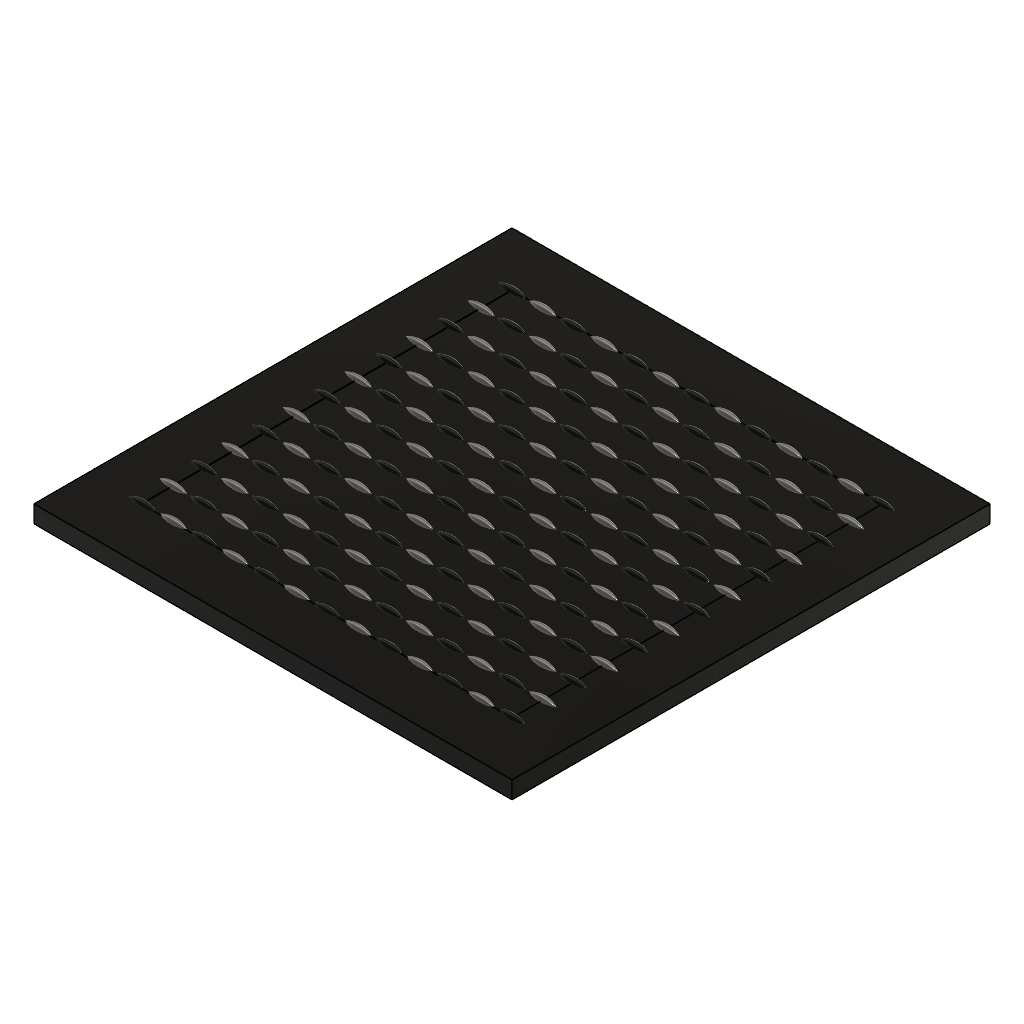
SCENE-draft (Autodesk Fusion 360 design; units mm, degrees)
Autodesk Fusion 360 part; units mm, degrees
(part 1 of 2)
ref_plane "工作平面1" through (0, 0, -12) normal (0, 0, 1) x (1, 0, 0) in component "scene_board"
sketch "草图1" plane through (0, 0, -12) normal (0, 0, 1) x (1, 0, 0) in component "scene_board"
  line L0 (-165, -165) -> (165, -165)
  line L1 (165, -165) -> (165, 165)
  line L2 (165, 165) -> (-165, 165)
  line L3 (-165, 165) -> (-165, -165)
extrude "拉伸1" add sketch "草图1" along normal blind 12 makes body 1 in component "scene_board"
ref_plane "工作平面2" through (0, 0, 0) normal (0, 0, 1) x (1, 0, 0) in component "scene_board"
sketch "草图2" plane through (0, 0, 0) normal (0, 0, 1) x (1, 0, 0) in component "scene_board"
  line L0 (-127.5, -127.9) -> (127.5, -127.9)
  line L1 (127.5, -127.9) -> (127.5, -127.1)
  line L2 (127.5, -127.1) -> (-127.5, -127.1)
  line L3 (-127.5, -127.1) -> (-127.5, -127.9)
  line L4 (-127.9, -127.5) -> (-127.1, -127.5)
  line L5 (-127.1, -127.5) -> (-127.1, 127.5)
  line L6 (-127.1, 127.5) -> (-127.9, 127.5)
  line L7 (-127.9, 127.5) -> (-127.9, -127.5)
  line L8 (-127.5, -106.65) -> (127.5, -106.65)
  line L9 (127.5, -106.65) -> (127.5, -105.85)
  line L10 (127.5, -105.85) -> (-127.5, -105.85)
  line L11 (-127.5, -105.85) -> (-127.5, -106.65)
  line L12 (-106.65, -127.5) -> (-105.85, -127.5)
  line L13 (-105.85, -127.5) -> (-105.85, 127.5)
  line L14 (-105.85, 127.5) -> (-106.65, 127.5)
  line L15 (-106.65, 127.5) -> (-106.65, -127.5)
  line L16 (-127.5, -85.4) -> (127.5, -85.4)
  line L17 (127.5, -85.4) -> (127.5, -84.6)
  line L18 (127.5, -84.6) -> (-127.5, -84.6)
  line L19 (-127.5, -84.6) -> (-127.5, -85.4)
  line L20 (-85.4, -127.5) -> (-84.6, -127.5)
  line L21 (-84.6, -127.5) -> (-84.6, 127.5)
  line L22 (-84.6, 127.5) -> (-85.4, 127.5)
  line L23 (-85.4, 127.5) -> (-85.4, -127.5)
  line L24 (-127.5, -64.15) -> (127.5, -64.15)
  line L25 (127.5, -64.15) -> (127.5, -63.35)
  line L26 (127.5, -63.35) -> (-127.5, -63.35)
  line L27 (-127.5, -63.35) -> (-127.5, -64.15)
  line L28 (-64.15, -127.5) -> (-63.35, -127.5)
  line L29 (-63.35, -127.5) -> (-63.35, 127.5)
  line L30 (-63.35, 127.5) -> (-64.15, 127.5)
  line L31 (-64.15, 127.5) -> (-64.15, -127.5)
  line L32 (-127.5, -42.9) -> (127.5, -42.9)
  line L33 (127.5, -42.9) -> (127.5, -42.1)
  line L34 (127.5, -42.1) -> (-127.5, -42.1)
  line L35 (-127.5, -42.1) -> (-127.5, -42.9)
  line L36 (-42.9, -127.5) -> (-42.1, -127.5)
  line L37 (-42.1, -127.5) -> (-42.1, 127.5)
  line L38 (-42.1, 127.5) -> (-42.9, 127.5)
  line L39 (-42.9, 127.5) -> (-42.9, -127.5)
  line L40 (-127.5, -21.65) -> (127.5, -21.65)
  line L41 (127.5, -21.65) -> (127.5, -20.85)
  line L42 (127.5, -20.85) -> (-127.5, -20.85)
  line L43 (-127.5, -20.85) -> (-127.5, -21.65)
  line L44 (-21.65, -127.5) -> (-20.85, -127.5)
  line L45 (-20.85, -127.5) -> (-20.85, 127.5)
  line L46 (-20.85, 127.5) -> (-21.65, 127.5)
  line L47 (-21.65, 127.5) -> (-21.65, -127.5)
  line L48 (-127.5, -0.4) -> (127.5, -0.4)
  line L49 (127.5, -0.4) -> (127.5, 0.4)
  line L50 (127.5, 0.4) -> (-127.5, 0.4)
  line L51 (-127.5, 0.4) -> (-127.5, -0.4)
  line L52 (-0.4, -127.5) -> (0.4, -127.5)
  line L53 (0.4, -127.5) -> (0.4, 127.5)
  line L54 (0.4, 127.5) -> (-0.4, 127.5)
  line L55 (-0.4, 127.5) -> (-0.4, -127.5)
  line L56 (-127.5, 20.85) -> (127.5, 20.85)
  line L57 (127.5, 20.85) -> (127.5, 21.65)
  line L58 (127.5, 21.65) -> (-127.5, 21.65)
  line L59 (-127.5, 21.65) -> (-127.5, 20.85)
  line L60 (20.85, -127.5) -> (21.65, -127.5)
  line L61 (21.65, -127.5) -> (21.65, 127.5)
  line L62 (21.65, 127.5) -> (20.85, 127.5)
  line L63 (20.85, 127.5) -> (20.85, -127.5)
  line L64 (-127.5, 42.1) -> (127.5, 42.1)
  line L65 (127.5, 42.1) -> (127.5, 42.9)
  line L66 (127.5, 42.9) -> (-127.5, 42.9)
  line L67 (-127.5, 42.9) -> (-127.5, 42.1)
  line L68 (42.1, -127.5) -> (42.9, -127.5)
  line L69 (42.9, -127.5) -> (42.9, 127.5)
  line L70 (42.9, 127.5) -> (42.1, 127.5)
  line L71 (42.1, 127.5) -> (42.1, -127.5)
  line L72 (-127.5, 63.35) -> (127.5, 63.35)
  line L73 (127.5, 63.35) -> (127.5, 64.15)
  line L74 (127.5, 64.15) -> (-127.5, 64.15)
  line L75 (-127.5, 64.15) -> (-127.5, 63.35)
  line L76 (63.35, -127.5) -> (64.15, -127.5)
  line L77 (64.15, -127.5) -> (64.15, 127.5)
  line L78 (64.15, 127.5) -> (63.35, 127.5)
  line L79 (63.35, 127.5) -> (63.35, -127.5)
  line L80 (-127.5, 84.6) -> (127.5, 84.6)
  line L81 (127.5, 84.6) -> (127.5, 85.4)
  line L82 (127.5, 85.4) -> (-127.5, 85.4)
  line L83 (-127.5, 85.4) -> (-127.5, 84.6)
  line L84 (84.6, -127.5) -> (85.4, -127.5)
  line L85 (85.4, -127.5) -> (85.4, 127.5)
  line L86 (85.4, 127.5) -> (84.6, 127.5)
  line L87 (84.6, 127.5) -> (84.6, -127.5)
  line L88 (-127.5, 105.85) -> (127.5, 105.85)
  line L89 (127.5, 105.85) -> (127.5, 106.65)
  line L90 (127.5, 106.65) -> (-127.5, 106.65)
  line L91 (-127.5, 106.65) -> (-127.5, 105.85)
  line L92 (105.85, -127.5) -> (106.65, -127.5)
  line L93 (106.65, -127.5) -> (106.65, 127.5)
  line L94 (106.65, 127.5) -> (105.85, 127.5)
  line L95 (105.85, 127.5) -> (105.85, -127.5)
  line L96 (-127.5, 127.1) -> (127.5, 127.1)
  line L97 (127.5, 127.1) -> (127.5, 127.9)
  line L98 (127.5, 127.9) -> (-127.5, 127.9)
  line L99 (-127.5, 127.9) -> (-127.5, 127.1)
  line L100 (127.1, -127.5) -> (127.9, -127.5)
  line L101 (127.9, -127.5) -> (127.9, 127.5)
  line L102 (127.9, 127.5) -> (127.1, 127.5)
  line L103 (127.1, 127.5) -> (127.1, -127.5)
extrude "拉伸2" cut sketch "草图2" against normal blind 0.3 bodies 1 in component "scene_board"
sketch "草图1 (2)" plane through (0, 0, 0) normal (0, 0, 1) x (1, 0, 0) in component "scene_go"
  line L0 (-139, -127.5) -> (-116, -127.5) construction
  arc A0 (-118, -127.5) -> (-137, -127.5) centre (-127.5, -146.4306) ccw
  arc A1 (-137, -127.5) -> (-118, -127.5) centre (-127.5, -108.5694) ccw
revolve "旋转1" add sketch "草图1 (2)" angle 360 about axis through (-139, -127.5, 0) along (1, 0, 0) separate body makes body 2 in component "scene_go"
sketch "草图2 (2)" plane through (0, 0, 0) normal (0, 0, 1) x (1, 0, 0) in component "scene_go"
  line L0 (-139, -106.25) -> (-116, -106.25) construction
  arc A0 (-118, -106.25) -> (-137, -106.25) centre (-127.5, -125.1806) ccw
  arc A1 (-137, -106.25) -> (-118, -106.25) centre (-127.5, -87.3194) ccw
revolve "旋转2" add sketch "草图2 (2)" angle 360 about axis through (-139, -106.25, 0) along (1, 0, 0) separate body makes body 3 in component "scene_go"
sketch "草图3" plane through (0, 0, 0) normal (0, 0, 1) x (1, 0, 0) in component "scene_go"
  line L0 (-139, -85) -> (-116, -85) construction
  arc A0 (-118, -85) -> (-137, -85) centre (-127.5, -103.9306) ccw
  arc A1 (-137, -85) -> (-118, -85) centre (-127.5, -66.0694) ccw
revolve "旋转3" add sketch "草图3" angle 360 about axis through (-139, -85, 0) along (1, 0, 0) separate body makes body 4 in component "scene_go"
sketch "草图4" plane through (0, 0, 0) normal (0, 0, 1) x (1, 0, 0) in component "scene_go"
  line L0 (-139, -63.75) -> (-116, -63.75) construction
  arc A0 (-118, -63.75) -> (-137, -63.75) centre (-127.5, -82.6806) ccw
  arc A1 (-137, -63.75) -> (-118, -63.75) centre (-127.5, -44.8194) ccw
revolve "旋转4" add sketch "草图4" angle 360 about axis through (-139, -63.75, 0) along (1, 0, 0) separate body makes body 5 in component "scene_go"
sketch "草图5" plane through (0, 0, 0) normal (0, 0, 1) x (1, 0, 0) in component "scene_go"
  line L0 (-139, -42.5) -> (-116, -42.5) construction
  arc A0 (-118, -42.5) -> (-137, -42.5) centre (-127.5, -61.4306) ccw
  arc A1 (-137, -42.5) -> (-118, -42.5) centre (-127.5, -23.5694) ccw
revolve "旋转5" add sketch "草图5" angle 360 about axis through (-139, -42.5, 0) along (1, 0, 0) separate body makes body 6 in component "scene_go"
sketch "草图6" plane through (0, 0, 0) normal (0, 0, 1) x (1, 0, 0) in component "scene_go"
  line L0 (-139, -21.25) -> (-116, -21.25) construction
  arc A0 (-118, -21.25) -> (-137, -21.25) centre (-127.5, -40.1806) ccw
  arc A1 (-137, -21.25) -> (-118, -21.25) centre (-127.5, -2.3194) ccw
revolve "旋转6" add sketch "草图6" angle 360 about axis through (-139, -21.25, 0) along (1, 0, 0) separate body makes body 7 in component "scene_go"
sketch "草图7" plane through (0, 0, 0) normal (0, 0, 1) x (1, 0, 0) in component "scene_go"
  line L0 (-139, 0) -> (-116, 0) construction
  arc A0 (-118, 0) -> (-137, 0) centre (-127.5, -18.9306) ccw
  arc A1 (-137, 0) -> (-118, 0) centre (-127.5, 18.9306) ccw
revolve "旋转7" add sketch "草图7" angle 360 about axis through (-139, 0, 0) along (1, 0, 0) separate body makes body 8 in component "scene_go"
sketch "草图8" plane through (0, 0, 0) normal (0, 0, 1) x (1, 0, 0) in component "scene_go"
  line L0 (-139, 21.25) -> (-116, 21.25) construction
  arc A0 (-118, 21.25) -> (-137, 21.25) centre (-127.5, 2.3194) ccw
  arc A1 (-137, 21.25) -> (-118, 21.25) centre (-127.5, 40.1806) ccw
revolve "旋转8" add sketch "草图8" angle 360 about axis through (-139, 21.25, 0) along (1, 0, 0) separate body makes body 9 in component "scene_go"
sketch "草图9" plane through (0, 0, 0) normal (0, 0, 1) x (1, 0, 0) in component "scene_go"
  line L0 (-139, 42.5) -> (-116, 42.5) construction
  arc A0 (-118, 42.5) -> (-137, 42.5) centre (-127.5, 23.5694) ccw
  arc A1 (-137, 42.5) -> (-118, 42.5) centre (-127.5, 61.4306) ccw
revolve "旋转9" add sketch "草图9" angle 360 about axis through (-139, 42.5, 0) along (1, 0, 0) separate body makes body 10 in component "scene_go"
sketch "草图10" plane through (0, 0, 0) normal (0, 0, 1) x (1, 0, 0) in component "scene_go"
  line L0 (-139, 63.75) -> (-116, 63.75) construction
  arc A0 (-118, 63.75) -> (-137, 63.75) centre (-127.5, 44.8194) ccw
  arc A1 (-137, 63.75) -> (-118, 63.75) centre (-127.5, 82.6806) ccw
revolve "旋转10" add sketch "草图10" angle 360 about axis through (-139, 63.75, 0) along (1, 0, 0) separate body makes body 11 in component "scene_go"
sketch "草图11" plane through (0, 0, 0) normal (0, 0, 1) x (1, 0, 0) in component "scene_go"
  line L0 (-139, 85) -> (-116, 85) construction
  arc A0 (-118, 85) -> (-137, 85) centre (-127.5, 66.0694) ccw
  arc A1 (-137, 85) -> (-118, 85) centre (-127.5, 103.9306) ccw
revolve "旋转11" add sketch "草图11" angle 360 about axis through (-139, 85, 0) along (1, 0, 0) separate body makes body 12 in component "scene_go"
sketch "草图12" plane through (0, 0, 0) normal (0, 0, 1) x (1, 0, 0) in component "scene_go"
  line L0 (-139, 106.25) -> (-116, 106.25) construction
  arc A0 (-118, 106.25) -> (-137, 106.25) centre (-127.5, 87.3194) ccw
  arc A1 (-137, 106.25) -> (-118, 106.25) centre (-127.5, 125.1806) ccw
revolve "旋转12" add sketch "草图12" angle 360 about axis through (-139, 106.25, 0) along (1, 0, 0) separate body makes body 13 in component "scene_go"
sketch "草图13" plane through (0, 0, 0) normal (0, 0, 1) x (1, 0, 0) in component "scene_go"
  line L0 (-139, 127.5) -> (-116, 127.5) construction
  arc A0 (-118, 127.5) -> (-137, 127.5) centre (-127.5, 108.5694) ccw
  arc A1 (-137, 127.5) -> (-118, 127.5) centre (-127.5, 146.4306) ccw
revolve "旋转13" add sketch "草图13" angle 360 about axis through (-139, 127.5, 0) along (1, 0, 0) separate body makes body 14 in component "scene_go"
sketch "草图14" plane through (0, 0, 0) normal (0, 0, 1) x (1, 0, 0) in component "scene_go"
  line L0 (-117.75, -127.5) -> (-94.75, -127.5) construction
  arc A0 (-96.75, -127.5) -> (-115.75, -127.5) centre (-106.25, -146.4306) ccw
  arc A1 (-115.75, -127.5) -> (-96.75, -127.5) centre (-106.25, -108.5694) ccw
revolve "旋转14" add sketch "草图14" angle 360 about axis through (-117.75, -127.5, 0) along (1, 0, 0) separate body makes body 15 in component "scene_go"
sketch "草图15" plane through (0, 0, 0) normal (0, 0, 1) x (1, 0, 0) in component "scene_go"
  line L0 (-117.75, -106.25) -> (-94.75, -106.25) construction
  arc A0 (-96.75, -106.25) -> (-115.75, -106.25) centre (-106.25, -125.1806) ccw
  arc A1 (-115.75, -106.25) -> (-96.75, -106.25) centre (-106.25, -87.3194) ccw
revolve "旋转15" add sketch "草图15" angle 360 about axis through (-117.75, -106.25, 0) along (1, 0, 0) separate body makes body 16 in component "scene_go"
sketch "草图16" plane through (0, 0, 0) normal (0, 0, 1) x (1, 0, 0) in component "scene_go"
  line L0 (-117.75, -85) -> (-94.75, -85) construction
  arc A0 (-96.75, -85) -> (-115.75, -85) centre (-106.25, -103.9306) ccw
  arc A1 (-115.75, -85) -> (-96.75, -85) centre (-106.25, -66.0694) ccw
revolve "旋转16" add sketch "草图16" angle 360 about axis through (-117.75, -85, 0) along (1, 0, 0) separate body makes body 17 in component "scene_go"
sketch "草图17" plane through (0, 0, 0) normal (0, 0, 1) x (1, 0, 0) in component "scene_go"
  line L0 (-117.75, -63.75) -> (-94.75, -63.75) construction
  arc A0 (-96.75, -63.75) -> (-115.75, -63.75) centre (-106.25, -82.6806) ccw
  arc A1 (-115.75, -63.75) -> (-96.75, -63.75) centre (-106.25, -44.8194) ccw
revolve "旋转17" add sketch "草图17" angle 360 about axis through (-117.75, -63.75, 0) along (1, 0, 0) separate body makes body 18 in component "scene_go"
sketch "草图18" plane through (0, 0, 0) normal (0, 0, 1) x (1, 0, 0) in component "scene_go"
  line L0 (-117.75, -42.5) -> (-94.75, -42.5) construction
  arc A0 (-96.75, -42.5) -> (-115.75, -42.5) centre (-106.25, -61.4306) ccw
  arc A1 (-115.75, -42.5) -> (-96.75, -42.5) centre (-106.25, -23.5694) ccw
revolve "旋转18" add sketch "草图18" angle 360 about axis through (-117.75, -42.5, 0) along (1, 0, 0) separate body makes body 19 in component "scene_go"
sketch "草图19" plane through (0, 0, 0) normal (0, 0, 1) x (1, 0, 0) in component "scene_go"
  line L0 (-117.75, -21.25) -> (-94.75, -21.25) construction
  arc A0 (-96.75, -21.25) -> (-115.75, -21.25) centre (-106.25, -40.1806) ccw
  arc A1 (-115.75, -21.25) -> (-96.75, -21.25) centre (-106.25, -2.3194) ccw
revolve "旋转19" add sketch "草图19" angle 360 about axis through (-117.75, -21.25, 0) along (1, 0, 0) separate body makes body 20 in component "scene_go"
sketch "草图20" plane through (0, 0, 0) normal (0, 0, 1) x (1, 0, 0) in component "scene_go"
  line L0 (-117.75, 0) -> (-94.75, 0) construction
  arc A0 (-96.75, 0) -> (-115.75, 0) centre (-106.25, -18.9306) ccw
  arc A1 (-115.75, 0) -> (-96.75, 0) centre (-106.25, 18.9306) ccw
revolve "旋转20" add sketch "草图20" angle 360 about axis through (-117.75, 0, 0) along (1, 0, 0) separate body makes body 21 in component "scene_go"
sketch "草图21" plane through (0, 0, 0) normal (0, 0, 1) x (1, 0, 0) in component "scene_go"
  line L0 (-117.75, 21.25) -> (-94.75, 21.25) construction
  arc A0 (-96.75, 21.25) -> (-115.75, 21.25) centre (-106.25, 2.3194) ccw
  arc A1 (-115.75, 21.25) -> (-96.75, 21.25) centre (-106.25, 40.1806) ccw
revolve "旋转21" add sketch "草图21" angle 360 about axis through (-117.75, 21.25, 0) along (1, 0, 0) separate body makes body 22 in component "scene_go"
sketch "草图22" plane through (0, 0, 0) normal (0, 0, 1) x (1, 0, 0) in component "scene_go"
  line L0 (-117.75, 42.5) -> (-94.75, 42.5) construction
  arc A0 (-96.75, 42.5) -> (-115.75, 42.5) centre (-106.25, 23.5694) ccw
  arc A1 (-115.75, 42.5) -> (-96.75, 42.5) centre (-106.25, 61.4306) ccw
revolve "旋转22" add sketch "草图22" angle 360 about axis through (-117.75, 42.5, 0) along (1, 0, 0) separate body makes body 23 in component "scene_go"
sketch "草图23" plane through (0, 0, 0) normal (0, 0, 1) x (1, 0, 0) in component "scene_go"
  line L0 (-117.75, 63.75) -> (-94.75, 63.75) construction
  arc A0 (-96.75, 63.75) -> (-115.75, 63.75) centre (-106.25, 44.8194) ccw
  arc A1 (-115.75, 63.75) -> (-96.75, 63.75) centre (-106.25, 82.6806) ccw
revolve "旋转23" add sketch "草图23" angle 360 about axis through (-117.75, 63.75, 0) along (1, 0, 0) separate body makes body 24 in component "scene_go"
sketch "草图24" plane through (0, 0, 0) normal (0, 0, 1) x (1, 0, 0) in component "scene_go"
  line L0 (-117.75, 85) -> (-94.75, 85) construction
  arc A0 (-96.75, 85) -> (-115.75, 85) centre (-106.25, 66.0694) ccw
  arc A1 (-115.75, 85) -> (-96.75, 85) centre (-106.25, 103.9306) ccw
revolve "旋转24" add sketch "草图24" angle 360 about axis through (-117.75, 85, 0) along (1, 0, 0) separate body makes body 25 in component "scene_go"
sketch "草图25" plane through (0, 0, 0) normal (0, 0, 1) x (1, 0, 0) in component "scene_go"
  line L0 (-117.75, 106.25) -> (-94.75, 106.25) construction
  arc A0 (-96.75, 106.25) -> (-115.75, 106.25) centre (-106.25, 87.3194) ccw
  arc A1 (-115.75, 106.25) -> (-96.75, 106.25) centre (-106.25, 125.1806) ccw
revolve "旋转25" add sketch "草图25" angle 360 about axis through (-117.75, 106.25, 0) along (1, 0, 0) separate body makes body 26 in component "scene_go"
sketch "草图26" plane through (0, 0, 0) normal (0, 0, 1) x (1, 0, 0) in component "scene_go"
  line L0 (-117.75, 127.5) -> (-94.75, 127.5) construction
  arc A0 (-96.75, 127.5) -> (-115.75, 127.5) centre (-106.25, 108.5694) ccw
  arc A1 (-115.75, 127.5) -> (-96.75, 127.5) centre (-106.25, 146.4306) ccw
revolve "旋转26" add sketch "草图26" angle 360 about axis through (-117.75, 127.5, 0) along (1, 0, 0) separate body makes body 27 in component "scene_go"
sketch "草图27" plane through (0, 0, 0) normal (0, 0, 1) x (1, 0, 0) in component "scene_go"
  line L0 (-96.5, -127.5) -> (-73.5, -127.5) construction
  arc A0 (-75.5, -127.5) -> (-94.5, -127.5) centre (-85, -146.4306) ccw
  arc A1 (-94.5, -127.5) -> (-75.5, -127.5) centre (-85, -108.5694) ccw
revolve "旋转27" add sketch "草图27" angle 360 about axis through (-96.5, -127.5, 0) along (1, 0, 0) separate body makes body 28 in component "scene_go"
sketch "草图28" plane through (0, 0, 0) normal (0, 0, 1) x (1, 0, 0) in component "scene_go"
  line L0 (-96.5, -106.25) -> (-73.5, -106.25) construction
  arc A0 (-75.5, -106.25) -> (-94.5, -106.25) centre (-85, -125.1806) ccw
  arc A1 (-94.5, -106.25) -> (-75.5, -106.25) centre (-85, -87.3194) ccw
revolve "旋转28" add sketch "草图28" angle 360 about axis through (-96.5, -106.25, 0) along (1, 0, 0) separate body makes body 29 in component "scene_go"
sketch "草图29" plane through (0, 0, 0) normal (0, 0, 1) x (1, 0, 0) in component "scene_go"
  line L0 (-96.5, -85) -> (-73.5, -85) construction
  arc A0 (-75.5, -85) -> (-94.5, -85) centre (-85, -103.9306) ccw
  arc A1 (-94.5, -85) -> (-75.5, -85) centre (-85, -66.0694) ccw
revolve "旋转29" add sketch "草图29" angle 360 about axis through (-96.5, -85, 0) along (1, 0, 0) separate body makes body 30 in component "scene_go"
sketch "草图30" plane through (0, 0, 0) normal (0, 0, 1) x (1, 0, 0) in component "scene_go"
  line L0 (-96.5, -63.75) -> (-73.5, -63.75) construction
  arc A0 (-75.5, -63.75) -> (-94.5, -63.75) centre (-85, -82.6806) ccw
  arc A1 (-94.5, -63.75) -> (-75.5, -63.75) centre (-85, -44.8194) ccw
revolve "旋转30" add sketch "草图30" angle 360 about axis through (-96.5, -63.75, 0) along (1, 0, 0) separate body makes body 31 in component "scene_go"
sketch "草图31" plane through (0, 0, 0) normal (0, 0, 1) x (1, 0, 0) in component "scene_go"
  line L0 (-96.5, -42.5) -> (-73.5, -42.5) construction
  arc A0 (-75.5, -42.5) -> (-94.5, -42.5) centre (-85, -61.4306) ccw
  arc A1 (-94.5, -42.5) -> (-75.5, -42.5) centre (-85, -23.5694) ccw
revolve "旋转31" add sketch "草图31" angle 360 about axis through (-96.5, -42.5, 0) along (1, 0, 0) separate body makes body 32 in component "scene_go"
sketch "草图32" plane through (0, 0, 0) normal (0, 0, 1) x (1, 0, 0) in component "scene_go"
  line L0 (-96.5, -21.25) -> (-73.5, -21.25) construction
  arc A0 (-75.5, -21.25) -> (-94.5, -21.25) centre (-85, -40.1806) ccw
  arc A1 (-94.5, -21.25) -> (-75.5, -21.25) centre (-85, -2.3194) ccw
revolve "旋转32" add sketch "草图32" angle 360 about axis through (-96.5, -21.25, 0) along (1, 0, 0) separate body makes body 33 in component "scene_go"
sketch "草图33" plane through (0, 0, 0) normal (0, 0, 1) x (1, 0, 0) in component "scene_go"
  line L0 (-96.5, 0) -> (-73.5, 0) construction
  arc A0 (-75.5, 0) -> (-94.5, 0) centre (-85, -18.9306) ccw
  arc A1 (-94.5, 0) -> (-75.5, 0) centre (-85, 18.9306) ccw
revolve "旋转33" add sketch "草图33" angle 360 about axis through (-96.5, 0, 0) along (1, 0, 0) separate body makes body 34 in component "scene_go"
sketch "草图34" plane through (0, 0, 0) normal (0, 0, 1) x (1, 0, 0) in component "scene_go"
  line L0 (-96.5, 21.25) -> (-73.5, 21.25) construction
  arc A0 (-75.5, 21.25) -> (-94.5, 21.25) centre (-85, 2.3194) ccw
  arc A1 (-94.5, 21.25) -> (-75.5, 21.25) centre (-85, 40.1806) ccw
revolve "旋转34" add sketch "草图34" angle 360 about axis through (-96.5, 21.25, 0) along (1, 0, 0) separate body makes body 35 in component "scene_go"
sketch "草图35" plane through (0, 0, 0) normal (0, 0, 1) x (1, 0, 0) in component "scene_go"
  line L0 (-96.5, 42.5) -> (-73.5, 42.5) construction
  arc A0 (-75.5, 42.5) -> (-94.5, 42.5) centre (-85, 23.5694) ccw
  arc A1 (-94.5, 42.5) -> (-75.5, 42.5) centre (-85, 61.4306) ccw
revolve "旋转35" add sketch "草图35" angle 360 about axis through (-96.5, 42.5, 0) along (1, 0, 0) separate body makes body 36 in component "scene_go"
sketch "草图36" plane through (0, 0, 0) normal (0, 0, 1) x (1, 0, 0) in component "scene_go"
  line L0 (-96.5, 63.75) -> (-73.5, 63.75) construction
  arc A0 (-75.5, 63.75) -> (-94.5, 63.75) centre (-85, 44.8194) ccw
  arc A1 (-94.5, 63.75) -> (-75.5, 63.75) centre (-85, 82.6806) ccw
revolve "旋转36" add sketch "草图36" angle 360 about axis through (-96.5, 63.75, 0) along (1, 0, 0) separate body makes body 37 in component "scene_go"
sketch "草图37" plane through (0, 0, 0) normal (0, 0, 1) x (1, 0, 0) in component "scene_go"
  line L0 (-96.5, 85) -> (-73.5, 85) construction
  arc A0 (-75.5, 85) -> (-94.5, 85) centre (-85, 66.0694) ccw
  arc A1 (-94.5, 85) -> (-75.5, 85) centre (-85, 103.9306) ccw
revolve "旋转37" add sketch "草图37" angle 360 about axis through (-96.5, 85, 0) along (1, 0, 0) separate body makes body 38 in component "scene_go"
sketch "草图38" plane through (0, 0, 0) normal (0, 0, 1) x (1, 0, 0) in component "scene_go"
  line L0 (-96.5, 106.25) -> (-73.5, 106.25) construction
  arc A0 (-75.5, 106.25) -> (-94.5, 106.25) centre (-85, 87.3194) ccw
  arc A1 (-94.5, 106.25) -> (-75.5, 106.25) centre (-85, 125.1806) ccw
revolve "旋转38" add sketch "草图38" angle 360 about axis through (-96.5, 106.25, 0) along (1, 0, 0) separate body makes body 39 in component "scene_go"
sketch "草图39" plane through (0, 0, 0) normal (0, 0, 1) x (1, 0, 0) in component "scene_go"
  line L0 (-96.5, 127.5) -> (-73.5, 127.5) construction
  arc A0 (-75.5, 127.5) -> (-94.5, 127.5) centre (-85, 108.5694) ccw
  arc A1 (-94.5, 127.5) -> (-75.5, 127.5) centre (-85, 146.4306) ccw
revolve "旋转39" add sketch "草图39" angle 360 about axis through (-96.5, 127.5, 0) along (1, 0, 0) separate body makes body 40 in component "scene_go"
sketch "草图40" plane through (0, 0, 0) normal (0, 0, 1) x (1, 0, 0) in component "scene_go"
  line L0 (-75.25, -127.5) -> (-52.25, -127.5) construction
  arc A0 (-54.25, -127.5) -> (-73.25, -127.5) centre (-63.75, -146.4306) ccw
  arc A1 (-73.25, -127.5) -> (-54.25, -127.5) centre (-63.75, -108.5694) ccw
revolve "旋转40" add sketch "草图40" angle 360 about axis through (-75.25, -127.5, 0) along (1, 0, 0) separate body makes body 41 in component "scene_go"
sketch "草图41" plane through (0, 0, 0) normal (0, 0, 1) x (1, 0, 0) in component "scene_go"
  line L0 (-75.25, -106.25) -> (-52.25, -106.25) construction
  arc A0 (-54.25, -106.25) -> (-73.25, -106.25) centre (-63.75, -125.1806) ccw
  arc A1 (-73.25, -106.25) -> (-54.25, -106.25) centre (-63.75, -87.3194) ccw
revolve "旋转41" add sketch "草图41" angle 360 about axis through (-75.25, -106.25, 0) along (1, 0, 0) separate body makes body 42 in component "scene_go"
sketch "草图42" plane through (0, 0, 0) normal (0, 0, 1) x (1, 0, 0) in component "scene_go"
  line L0 (-75.25, -85) -> (-52.25, -85) construction
  arc A0 (-54.25, -85) -> (-73.25, -85) centre (-63.75, -103.9306) ccw
  arc A1 (-73.25, -85) -> (-54.25, -85) centre (-63.75, -66.0694) ccw
revolve "旋转42" add sketch "草图42" angle 360 about axis through (-75.25, -85, 0) along (1, 0, 0) separate body makes body 43 in component "scene_go"
sketch "草图43" plane through (0, 0, 0) normal (0, 0, 1) x (1, 0, 0) in component "scene_go"
  line L0 (-75.25, -63.75) -> (-52.25, -63.75) construction
  arc A0 (-54.25, -63.75) -> (-73.25, -63.75) centre (-63.75, -82.6806) ccw
  arc A1 (-73.25, -63.75) -> (-54.25, -63.75) centre (-63.75, -44.8194) ccw
revolve "旋转43" add sketch "草图43" angle 360 about axis through (-75.25, -63.75, 0) along (1, 0, 0) separate body makes body 44 in component "scene_go"
sketch "草图44" plane through (0, 0, 0) normal (0, 0, 1) x (1, 0, 0) in component "scene_go"
  line L0 (-75.25, -42.5) -> (-52.25, -42.5) construction
  arc A0 (-54.25, -42.5) -> (-73.25, -42.5) centre (-63.75, -61.4306) ccw
  arc A1 (-73.25, -42.5) -> (-54.25, -42.5) centre (-63.75, -23.5694) ccw
revolve "旋转44" add sketch "草图44" angle 360 about axis through (-75.25, -42.5, 0) along (1, 0, 0) separate body makes body 45 in component "scene_go"
sketch "草图45" plane through (0, 0, 0) normal (0, 0, 1) x (1, 0, 0) in component "scene_go"
  line L0 (-75.25, -21.25) -> (-52.25, -21.25) construction
  arc A0 (-54.25, -21.25) -> (-73.25, -21.25) centre (-63.75, -40.1806) ccw
  arc A1 (-73.25, -21.25) -> (-54.25, -21.25) centre (-63.75, -2.3194) ccw
revolve "旋转45" add sketch "草图45" angle 360 about axis through (-75.25, -21.25, 0) along (1, 0, 0) separate body makes body 46 in component "scene_go"
sketch "草图46" plane through (0, 0, 0) normal (0, 0, 1) x (1, 0, 0) in component "scene_go"
  line L0 (-75.25, 0) -> (-52.25, 0) construction
  arc A0 (-54.25, 0) -> (-73.25, 0) centre (-63.75, -18.9306) ccw
  arc A1 (-73.25, 0) -> (-54.25, 0) centre (-63.75, 18.9306) ccw
revolve "旋转46" add sketch "草图46" angle 360 about axis through (-75.25, 0, 0) along (1, 0, 0) separate body makes body 47 in component "scene_go"
sketch "草图47" plane through (0, 0, 0) normal (0, 0, 1) x (1, 0, 0) in component "scene_go"
  line L0 (-75.25, 21.25) -> (-52.25, 21.25) construction
  arc A0 (-54.25, 21.25) -> (-73.25, 21.25) centre (-63.75, 2.3194) ccw
  arc A1 (-73.25, 21.25) -> (-54.25, 21.25) centre (-63.75, 40.1806) ccw
revolve "旋转47" add sketch "草图47" angle 360 about axis through (-75.25, 21.25, 0) along (1, 0, 0) separate body makes body 48 in component "scene_go"
sketch "草图48" plane through (0, 0, 0) normal (0, 0, 1) x (1, 0, 0) in component "scene_go"
  line L0 (-75.25, 42.5) -> (-52.25, 42.5) construction
  arc A0 (-54.25, 42.5) -> (-73.25, 42.5) centre (-63.75, 23.5694) ccw
  arc A1 (-73.25, 42.5) -> (-54.25, 42.5) centre (-63.75, 61.4306) ccw
revolve "旋转48" add sketch "草图48" angle 360 about axis through (-75.25, 42.5, 0) along (1, 0, 0) separate body makes body 49 in component "scene_go"
sketch "草图49" plane through (0, 0, 0) normal (0, 0, 1) x (1, 0, 0) in component "scene_go"
  line L0 (-75.25, 63.75) -> (-52.25, 63.75) construction
  arc A0 (-54.25, 63.75) -> (-73.25, 63.75) centre (-63.75, 44.8194) ccw
  arc A1 (-73.25, 63.75) -> (-54.25, 63.75) centre (-63.75, 82.6806) ccw
revolve "旋转49" add sketch "草图49" angle 360 about axis through (-75.25, 63.75, 0) along (1, 0, 0) separate body makes body 50 in component "scene_go"
sketch "草图50" plane through (0, 0, 0) normal (0, 0, 1) x (1, 0, 0) in component "scene_go"
  line L0 (-75.25, 85) -> (-52.25, 85) construction
  arc A0 (-54.25, 85) -> (-73.25, 85) centre (-63.75, 66.0694) ccw
  arc A1 (-73.25, 85) -> (-54.25, 85) centre (-63.75, 103.9306) ccw
revolve "旋转50" add sketch "草图50" angle 360 about axis through (-75.25, 85, 0) along (1, 0, 0) separate body makes body 51 in component "scene_go"
sketch "草图51" plane through (0, 0, 0) normal (0, 0, 1) x (1, 0, 0) in component "scene_go"
  line L0 (-75.25, 106.25) -> (-52.25, 106.25) construction
  arc A0 (-54.25, 106.25) -> (-73.25, 106.25) centre (-63.75, 87.3194) ccw
  arc A1 (-73.25, 106.25) -> (-54.25, 106.25) centre (-63.75, 125.1806) ccw
revolve "旋转51" add sketch "草图51" angle 360 about axis through (-75.25, 106.25, 0) along (1, 0, 0) separate body makes body 52 in component "scene_go"
sketch "草图52" plane through (0, 0, 0) normal (0, 0, 1) x (1, 0, 0) in component "scene_go"
  line L0 (-75.25, 127.5) -> (-52.25, 127.5) construction
  arc A0 (-54.25, 127.5) -> (-73.25, 127.5) centre (-63.75, 108.5694) ccw
  arc A1 (-73.25, 127.5) -> (-54.25, 127.5) centre (-63.75, 146.4306) ccw
revolve "旋转52" add sketch "草图52" angle 360 about axis through (-75.25, 127.5, 0) along (1, 0, 0) separate body makes body 53 in component "scene_go"
sketch "草图53" plane through (0, 0, 0) normal (0, 0, 1) x (1, 0, 0) in component "scene_go"
  line L0 (-54, -127.5) -> (-31, -127.5) construction
  arc A0 (-33, -127.5) -> (-52, -127.5) centre (-42.5, -146.4306) ccw
  arc A1 (-52, -127.5) -> (-33, -127.5) centre (-42.5, -108.5694) ccw
revolve "旋转53" add sketch "草图53" angle 360 about axis through (-54, -127.5, 0) along (1, 0, 0) separate body makes body 54 in component "scene_go"
sketch "草图54" plane through (0, 0, 0) normal (0, 0, 1) x (1, 0, 0) in component "scene_go"
  line L0 (-54, -106.25) -> (-31, -106.25) construction
  arc A0 (-33, -106.25) -> (-52, -106.25) centre (-42.5, -125.1806) ccw
  arc A1 (-52, -106.25) -> (-33, -106.25) centre (-42.5, -87.3194) ccw
revolve "旋转54" add sketch "草图54" angle 360 about axis through (-54, -106.25, 0) along (1, 0, 0) separate body makes body 55 in component "scene_go"
sketch "草图55" plane through (0, 0, 0) normal (0, 0, 1) x (1, 0, 0) in component "scene_go"
  line L0 (-54, -85) -> (-31, -85) construction
  arc A0 (-33, -85) -> (-52, -85) centre (-42.5, -103.9306) ccw
  arc A1 (-52, -85) -> (-33, -85) centre (-42.5, -66.0694) ccw
revolve "旋转55" add sketch "草图55" angle 360 about axis through (-54, -85, 0) along (1, 0, 0) separate body makes body 56 in component "scene_go"
sketch "草图56" plane through (0, 0, 0) normal (0, 0, 1) x (1, 0, 0) in component "scene_go"
  line L0 (-54, -63.75) -> (-31, -63.75) construction
  arc A0 (-33, -63.75) -> (-52, -63.75) centre (-42.5, -82.6806) ccw
  arc A1 (-52, -63.75) -> (-33, -63.75) centre (-42.5, -44.8194) ccw
revolve "旋转56" add sketch "草图56" angle 360 about axis through (-54, -63.75, 0) along (1, 0, 0) separate body makes body 57 in component "scene_go"
sketch "草图57" plane through (0, 0, 0) normal (0, 0, 1) x (1, 0, 0) in component "scene_go"
  line L0 (-54, -42.5) -> (-31, -42.5) construction
  arc A0 (-33, -42.5) -> (-52, -42.5) centre (-42.5, -61.4306) ccw
  arc A1 (-52, -42.5) -> (-33, -42.5) centre (-42.5, -23.5694) ccw
revolve "旋转57" add sketch "草图57" angle 360 about axis through (-54, -42.5, 0) along (1, 0, 0) separate body makes body 58 in component "scene_go"
sketch "草图58" plane through (0, 0, 0) normal (0, 0, 1) x (1, 0, 0) in component "scene_go"
  line L0 (-54, -21.25) -> (-31, -21.25) construction
  arc A0 (-33, -21.25) -> (-52, -21.25) centre (-42.5, -40.1806) ccw
  arc A1 (-52, -21.25) -> (-33, -21.25) centre (-42.5, -2.3194) ccw
revolve "旋转58" add sketch "草图58" angle 360 about axis through (-54, -21.25, 0) along (1, 0, 0) separate body makes body 59 in component "scene_go"
sketch "草图59" plane through (0, 0, 0) normal (0, 0, 1) x (1, 0, 0) in component "scene_go"
  line L0 (-54, 0) -> (-31, 0) construction
  arc A0 (-33, 0) -> (-52, 0) centre (-42.5, -18.9306) ccw
  arc A1 (-52, 0) -> (-33, 0) centre (-42.5, 18.9306) ccw
revolve "旋转59" add sketch "草图59" angle 360 about axis through (-54, 0, 0) along (1, 0, 0) separate body makes body 60 in component "scene_go"
sketch "草图60" plane through (0, 0, 0) normal (0, 0, 1) x (1, 0, 0) in component "scene_go"
  line L0 (-54, 21.25) -> (-31, 21.25) construction
  arc A0 (-33, 21.25) -> (-52, 21.25) centre (-42.5, 2.3194) ccw
  arc A1 (-52, 21.25) -> (-33, 21.25) centre (-42.5, 40.1806) ccw
revolve "旋转60" add sketch "草图60" angle 360 about axis through (-54, 21.25, 0) along (1, 0, 0) separate body makes body 61 in component "scene_go"
sketch "草图61" plane through (0, 0, 0) normal (0, 0, 1) x (1, 0, 0) in component "scene_go"
  line L0 (-54, 42.5) -> (-31, 42.5) construction
  arc A0 (-33, 42.5) -> (-52, 42.5) centre (-42.5, 23.5694) ccw
  arc A1 (-52, 42.5) -> (-33, 42.5) centre (-42.5, 61.4306) ccw
revolve "旋转61" add sketch "草图61" angle 360 about axis through (-54, 42.5, 0) along (1, 0, 0) separate body makes body 62 in component "scene_go"
sketch "草图62" plane through (0, 0, 0) normal (0, 0, 1) x (1, 0, 0) in component "scene_go"
  line L0 (-54, 63.75) -> (-31, 63.75) construction
  arc A0 (-33, 63.75) -> (-52, 63.75) centre (-42.5, 44.8194) ccw
  arc A1 (-52, 63.75) -> (-33, 63.75) centre (-42.5, 82.6806) ccw
revolve "旋转62" add sketch "草图62" angle 360 about axis through (-54, 63.75, 0) along (1, 0, 0) separate body makes body 63 in component "scene_go"
sketch "草图63" plane through (0, 0, 0) normal (0, 0, 1) x (1, 0, 0) in component "scene_go"
  line L0 (-54, 85) -> (-31, 85) construction
  arc A0 (-33, 85) -> (-52, 85) centre (-42.5, 66.0694) ccw
  arc A1 (-52, 85) -> (-33, 85) centre (-42.5, 103.9306) ccw
revolve "旋转63" add sketch "草图63" angle 360 about axis through (-54, 85, 0) along (1, 0, 0) separate body makes body 64 in component "scene_go"
sketch "草图64" plane through (0, 0, 0) normal (0, 0, 1) x (1, 0, 0) in component "scene_go"
  line L0 (-54, 106.25) -> (-31, 106.25) construction
  arc A0 (-33, 106.25) -> (-52, 106.25) centre (-42.5, 87.3194) ccw
  arc A1 (-52, 106.25) -> (-33, 106.25) centre (-42.5, 125.1806) ccw
revolve "旋转64" add sketch "草图64" angle 360 about axis through (-54, 106.25, 0) along (1, 0, 0) separate body makes body 65 in component "scene_go"
sketch "草图65" plane through (0, 0, 0) normal (0, 0, 1) x (1, 0, 0) in component "scene_go"
  line L0 (-54, 127.5) -> (-31, 127.5) construction
  arc A0 (-33, 127.5) -> (-52, 127.5) centre (-42.5, 108.5694) ccw
  arc A1 (-52, 127.5) -> (-33, 127.5) centre (-42.5, 146.4306) ccw
revolve "旋转65" add sketch "草图65" angle 360 about axis through (-54, 127.5, 0) along (1, 0, 0) separate body makes body 66 in component "scene_go"
sketch "草图66" plane through (0, 0, 0) normal (0, 0, 1) x (1, 0, 0) in component "scene_go"
  line L0 (-32.75, -127.5) -> (-9.75, -127.5) construction
  arc A0 (-11.75, -127.5) -> (-30.75, -127.5) centre (-21.25, -146.4306) ccw
  arc A1 (-30.75, -127.5) -> (-11.75, -127.5) centre (-21.25, -108.5694) ccw
revolve "旋转66" add sketch "草图66" angle 360 about axis through (-32.75, -127.5, 0) along (1, 0, 0) separate body makes body 67 in component "scene_go"
sketch "草图67" plane through (0, 0, 0) normal (0, 0, 1) x (1, 0, 0) in component "scene_go"
  line L0 (-32.75, -106.25) -> (-9.75, -106.25) construction
  arc A0 (-11.75, -106.25) -> (-30.75, -106.25) centre (-21.25, -125.1806) ccw
  arc A1 (-30.75, -106.25) -> (-11.75, -106.25) centre (-21.25, -87.3194) ccw
revolve "旋转67" add sketch "草图67" angle 360 about axis through (-32.75, -106.25, 0) along (1, 0, 0) separate body makes body 68 in component "scene_go"
sketch "草图68" plane through (0, 0, 0) normal (0, 0, 1) x (1, 0, 0) in component "scene_go"
  line L0 (-32.75, -85) -> (-9.75, -85) construction
  arc A0 (-11.75, -85) -> (-30.75, -85) centre (-21.25, -103.9306) ccw
  arc A1 (-30.75, -85) -> (-11.75, -85) centre (-21.25, -66.0694) ccw
revolve "旋转68" add sketch "草图68" angle 360 about axis through (-32.75, -85, 0) along (1, 0, 0) separate body makes body 69 in component "scene_go"
sketch "草图69" plane through (0, 0, 0) normal (0, 0, 1) x (1, 0, 0) in component "scene_go"
  line L0 (-32.75, -63.75) -> (-9.75, -63.75) construction
  arc A0 (-11.75, -63.75) -> (-30.75, -63.75) centre (-21.25, -82.6806) ccw
  arc A1 (-30.75, -63.75) -> (-11.75, -63.75) centre (-21.25, -44.8194) ccw
revolve "旋转69" add sketch "草图69" angle 360 about axis through (-32.75, -63.75, 0) along (1, 0, 0) separate body makes body 70 in component "scene_go"
sketch "草图70" plane through (0, 0, 0) normal (0, 0, 1) x (1, 0, 0) in component "scene_go"
  line L0 (-32.75, -42.5) -> (-9.75, -42.5) construction
  arc A0 (-11.75, -42.5) -> (-30.75, -42.5) centre (-21.25, -61.4306) ccw
  arc A1 (-30.75, -42.5) -> (-11.75, -42.5) centre (-21.25, -23.5694) ccw
revolve "旋转70" add sketch "草图70" angle 360 about axis through (-32.75, -42.5, 0) along (1, 0, 0) separate body makes body 71 in component "scene_go"
sketch "草图71" plane through (0, 0, 0) normal (0, 0, 1) x (1, 0, 0) in component "scene_go"
  line L0 (-32.75, -21.25) -> (-9.75, -21.25) construction
  arc A0 (-11.75, -21.25) -> (-30.75, -21.25) centre (-21.25, -40.1806) ccw
  arc A1 (-30.75, -21.25) -> (-11.75, -21.25) centre (-21.25, -2.3194) ccw
revolve "旋转71" add sketch "草图71" angle 360 about axis through (-32.75, -21.25, 0) along (1, 0, 0) separate body makes body 72 in component "scene_go"
sketch "草图72" plane through (0, 0, 0) normal (0, 0, 1) x (1, 0, 0) in component "scene_go"
  line L0 (-32.75, 0) -> (-9.75, 0) construction
  arc A0 (-11.75, 0) -> (-30.75, 0) centre (-21.25, -18.9306) ccw
  arc A1 (-30.75, 0) -> (-11.75, 0) centre (-21.25, 18.9306) ccw
revolve "旋转72" add sketch "草图72" angle 360 about axis through (-32.75, 0, 0) along (1, 0, 0) separate body makes body 73 in component "scene_go"
sketch "草图73" plane through (0, 0, 0) normal (0, 0, 1) x (1, 0, 0) in component "scene_go"
  line L0 (-32.75, 21.25) -> (-9.75, 21.25) construction
  arc A0 (-11.75, 21.25) -> (-30.75, 21.25) centre (-21.25, 2.3194) ccw
  arc A1 (-30.75, 21.25) -> (-11.75, 21.25) centre (-21.25, 40.1806) ccw
revolve "旋转73" add sketch "草图73" angle 360 about axis through (-32.75, 21.25, 0) along (1, 0, 0) separate body makes body 74 in component "scene_go"
sketch "草图74" plane through (0, 0, 0) normal (0, 0, 1) x (1, 0, 0) in component "scene_go"
  line L0 (-32.75, 42.5) -> (-9.75, 42.5) construction
  arc A0 (-11.75, 42.5) -> (-30.75, 42.5) centre (-21.25, 23.5694) ccw
  arc A1 (-30.75, 42.5) -> (-11.75, 42.5) centre (-21.25, 61.4306) ccw
revolve "旋转74" add sketch "草图74" angle 360 about axis through (-32.75, 42.5, 0) along (1, 0, 0) separate body makes body 75 in component "scene_go"
sketch "草图75" plane through (0, 0, 0) normal (0, 0, 1) x (1, 0, 0) in component "scene_go"
  line L0 (-32.75, 63.75) -> (-9.75, 63.75) construction
  arc A0 (-11.75, 63.75) -> (-30.75, 63.75) centre (-21.25, 44.8194) ccw
  arc A1 (-30.75, 63.75) -> (-11.75, 63.75) centre (-21.25, 82.6806) ccw
revolve "旋转75" add sketch "草图75" angle 360 about axis through (-32.75, 63.75, 0) along (1, 0, 0) separate body makes body 76 in component "scene_go"
sketch "草图76" plane through (0, 0, 0) normal (0, 0, 1) x (1, 0, 0) in component "scene_go"
  line L0 (-32.75, 85) -> (-9.75, 85) construction
  arc A0 (-11.75, 85) -> (-30.75, 85) centre (-21.25, 66.0694) ccw
  arc A1 (-30.75, 85) -> (-11.75, 85) centre (-21.25, 103.9306) ccw
revolve "旋转76" add sketch "草图76" angle 360 about axis through (-32.75, 85, 0) along (1, 0, 0) separate body makes body 77 in component "scene_go"
sketch "草图77" plane through (0, 0, 0) normal (0, 0, 1) x (1, 0, 0) in component "scene_go"
  line L0 (-32.75, 106.25) -> (-9.75, 106.25) construction
  arc A0 (-11.75, 106.25) -> (-30.75, 106.25) centre (-21.25, 87.3194) ccw
  arc A1 (-30.75, 106.25) -> (-11.75, 106.25) centre (-21.25, 125.1806) ccw
revolve "旋转77" add sketch "草图77" angle 360 about axis through (-32.75, 106.25, 0) along (1, 0, 0) separate body makes body 78 in component "scene_go"
sketch "草图78" plane through (0, 0, 0) normal (0, 0, 1) x (1, 0, 0) in component "scene_go"
  line L0 (-32.75, 127.5) -> (-9.75, 127.5) construction
  arc A0 (-11.75, 127.5) -> (-30.75, 127.5) centre (-21.25, 108.5694) ccw
  arc A1 (-30.75, 127.5) -> (-11.75, 127.5) centre (-21.25, 146.4306) ccw
revolve "旋转78" add sketch "草图78" angle 360 about axis through (-32.75, 127.5, 0) along (1, 0, 0) separate body makes body 79 in component "scene_go"
sketch "草图79" plane through (0, 0, 0) normal (0, 0, 1) x (1, 0, 0) in component "scene_go"
  line L0 (-11.5, -127.5) -> (11.5, -127.5) construction
  arc A0 (9.5, -127.5) -> (-9.5, -127.5) centre (0, -146.4306) ccw
  arc A1 (-9.5, -127.5) -> (9.5, -127.5) centre (0, -108.5694) ccw
revolve "旋转79" add sketch "草图79" angle 360 about axis through (-11.5, -127.5, 0) along (1, 0, 0) separate body makes body 80 in component "scene_go"
sketch "草图80" plane through (0, 0, 0) normal (0, 0, 1) x (1, 0, 0) in component "scene_go"
  line L0 (-11.5, -106.25) -> (11.5, -106.25) construction
  arc A0 (9.5, -106.25) -> (-9.5, -106.25) centre (0, -125.1806) ccw
  arc A1 (-9.5, -106.25) -> (9.5, -106.25) centre (0, -87.3194) ccw
revolve "旋转80" add sketch "草图80" angle 360 about axis through (-11.5, -106.25, 0) along (1, 0, 0) separate body makes body 81 in component "scene_go"
sketch "草图81" plane through (0, 0, 0) normal (0, 0, 1) x (1, 0, 0) in component "scene_go"
  line L0 (-11.5, -85) -> (11.5, -85) construction
  arc A0 (9.5, -85) -> (-9.5, -85) centre (0, -103.9306) ccw
  arc A1 (-9.5, -85) -> (9.5, -85) centre (0, -66.0694) ccw
revolve "旋转81" add sketch "草图81" angle 360 about axis through (-11.5, -85, 0) along (1, 0, 0) separate body makes body 82 in component "scene_go"
sketch "草图82" plane through (0, 0, 0) normal (0, 0, 1) x (1, 0, 0) in component "scene_go"
  line L0 (-11.5, -63.75) -> (11.5, -63.75) construction
  arc A0 (9.5, -63.75) -> (-9.5, -63.75) centre (0, -82.6806) ccw
  arc A1 (-9.5, -63.75) -> (9.5, -63.75) centre (0, -44.8194) ccw
revolve "旋转82" add sketch "草图82" angle 360 about axis through (-11.5, -63.75, 0) along (1, 0, 0) separate body makes body 83 in component "scene_go"
sketch "草图83" plane through (0, 0, 0) normal (0, 0, 1) x (1, 0, 0) in component "scene_go"
  line L0 (-11.5, -42.5) -> (11.5, -42.5) construction
  arc A0 (9.5, -42.5) -> (-9.5, -42.5) centre (0, -61.4306) ccw
  arc A1 (-9.5, -42.5) -> (9.5, -42.5) centre (0, -23.5694) ccw
revolve "旋转83" add sketch "草图83" angle 360 about axis through (-11.5, -42.5, 0) along (1, 0, 0) separate body makes body 84 in component "scene_go"
sketch "草图84" plane through (0, 0, 0) normal (0, 0, 1) x (1, 0, 0) in component "scene_go"
  line L0 (-11.5, -21.25) -> (11.5, -21.25) construction
  arc A0 (9.5, -21.25) -> (-9.5, -21.25) centre (0, -40.1806) ccw
  arc A1 (-9.5, -21.25) -> (9.5, -21.25) centre (0, -2.3194) ccw
revolve "旋转84" add sketch "草图84" angle 360 about axis through (-11.5, -21.25, 0) along (1, 0, 0) separate body makes body 85 in component "scene_go"
sketch "草图85" plane through (0, 0, 0) normal (0, 0, 1) x (1, 0, 0) in component "scene_go"
  line L0 (-11.5, 0) -> (11.5, 0) construction
  arc A0 (9.5, 0) -> (-9.5, 0) centre (0, -18.9306) ccw
  arc A1 (-9.5, 0) -> (9.5, 0) centre (0, 18.9306) ccw
revolve "旋转85" add sketch "草图85" angle 360 about axis through (-11.5, 0, 0) along (1, 0, 0) separate body makes body 86 in component "scene_go"
sketch "草图86" plane through (0, 0, 0) normal (0, 0, 1) x (1, 0, 0) in component "scene_go"
  line L0 (-11.5, 21.25) -> (11.5, 21.25) construction
  arc A0 (9.5, 21.25) -> (-9.5, 21.25) centre (0, 2.3194) ccw
  arc A1 (-9.5, 21.25) -> (9.5, 21.25) centre (0, 40.1806) ccw
revolve "旋转86" add sketch "草图86" angle 360 about axis through (-11.5, 21.25, 0) along (1, 0, 0) separate body makes body 87 in component "scene_go"
sketch "草图87" plane through (0, 0, 0) normal (0, 0, 1) x (1, 0, 0) in component "scene_go"
  line L0 (-11.5, 42.5) -> (11.5, 42.5) construction
  arc A0 (9.5, 42.5) -> (-9.5, 42.5) centre (0, 23.5694) ccw
  arc A1 (-9.5, 42.5) -> (9.5, 42.5) centre (0, 61.4306) ccw
revolve "旋转87" add sketch "草图87" angle 360 about axis through (-11.5, 42.5, 0) along (1, 0, 0) separate body makes body 88 in component "scene_go"
sketch "草图88" plane through (0, 0, 0) normal (0, 0, 1) x (1, 0, 0) in component "scene_go"
  line L0 (-11.5, 63.75) -> (11.5, 63.75) construction
  arc A0 (9.5, 63.75) -> (-9.5, 63.75) centre (0, 44.8194) ccw
  arc A1 (-9.5, 63.75) -> (9.5, 63.75) centre (0, 82.6806) ccw
revolve "旋转88" add sketch "草图88" angle 360 about axis through (-11.5, 63.75, 0) along (1, 0, 0) separate body makes body 89 in component "scene_go"
sketch "草图89" plane through (0, 0, 0) normal (0, 0, 1) x (1, 0, 0) in component "scene_go"
  line L0 (-11.5, 85) -> (11.5, 85) construction
  arc A0 (9.5, 85) -> (-9.5, 85) centre (0, 66.0694) ccw
  arc A1 (-9.5, 85) -> (9.5, 85) centre (0, 103.9306) ccw
revolve "旋转89" add sketch "草图89" angle 360 about axis through (-11.5, 85, 0) along (1, 0, 0) separate body makes body 90 in component "scene_go"
sketch "草图90" plane through (0, 0, 0) normal (0, 0, 1) x (1, 0, 0) in component "scene_go"
  line L0 (-11.5, 106.25) -> (11.5, 106.25) construction
  arc A0 (9.5, 106.25) -> (-9.5, 106.25) centre (0, 87.3194) ccw
  arc A1 (-9.5, 106.25) -> (9.5, 106.25) centre (0, 125.1806) ccw
revolve "旋转90" add sketch "草图90" angle 360 about axis through (-11.5, 106.25, 0) along (1, 0, 0) separate body makes body 91 in component "scene_go"
sketch "草图91" plane through (0, 0, 0) normal (0, 0, 1) x (1, 0, 0) in component "scene_go"
  line L0 (-11.5, 127.5) -> (11.5, 127.5) construction
  arc A0 (9.5, 127.5) -> (-9.5, 127.5) centre (0, 108.5694) ccw
  arc A1 (-9.5, 127.5) -> (9.5, 127.5) centre (0, 146.4306) ccw
revolve "旋转91" add sketch "草图91" angle 360 about axis through (-11.5, 127.5, 0) along (1, 0, 0) separate body makes body 92 in component "scene_go"
sketch "草图92" plane through (0, 0, 0) normal (0, 0, 1) x (1, 0, 0) in component "scene_go"
  line L0 (9.75, -127.5) -> (32.75, -127.5) construction
  arc A0 (30.75, -127.5) -> (11.75, -127.5) centre (21.25, -146.4306) ccw
  arc A1 (11.75, -127.5) -> (30.75, -127.5) centre (21.25, -108.5694) ccw
revolve "旋转92" add sketch "草图92" angle 360 about axis through (9.75, -127.5, 0) along (1, 0, 0) separate body makes body 93 in component "scene_go"
sketch "草图93" plane through (0, 0, 0) normal (0, 0, 1) x (1, 0, 0) in component "scene_go"
  line L0 (9.75, -106.25) -> (32.75, -106.25) construction
  arc A0 (30.75, -106.25) -> (11.75, -106.25) centre (21.25, -125.1806) ccw
  arc A1 (11.75, -106.25) -> (30.75, -106.25) centre (21.25, -87.3194) ccw
revolve "旋转93" add sketch "草图93" angle 360 about axis through (9.75, -106.25, 0) along (1, 0, 0) separate body makes body 94 in component "scene_go"
sketch "草图94" plane through (0, 0, 0) normal (0, 0, 1) x (1, 0, 0) in component "scene_go"
  line L0 (9.75, -85) -> (32.75, -85) construction
  arc A0 (30.75, -85) -> (11.75, -85) centre (21.25, -103.9306) ccw
  arc A1 (11.75, -85) -> (30.75, -85) centre (21.25, -66.0694) ccw
revolve "旋转94" add sketch "草图94" angle 360 about axis through (9.75, -85, 0) along (1, 0, 0) separate body makes body 95 in component "scene_go"
sketch "草图95" plane through (0, 0, 0) normal (0, 0, 1) x (1, 0, 0) in component "scene_go"
  line L0 (9.75, -63.75) -> (32.75, -63.75) construction
  arc A0 (30.75, -63.75) -> (11.75, -63.75) centre (21.25, -82.6806) ccw
  arc A1 (11.75, -63.75) -> (30.75, -63.75) centre (21.25, -44.8194) ccw
revolve "旋转95" add sketch "草图95" angle 360 about axis through (9.75, -63.75, 0) along (1, 0, 0) separate body makes body 96 in component "scene_go"
sketch "草图96" plane through (0, 0, 0) normal (0, 0, 1) x (1, 0, 0) in component "scene_go"
  line L0 (9.75, -42.5) -> (32.75, -42.5) construction
  arc A0 (30.75, -42.5) -> (11.75, -42.5) centre (21.25, -61.4306) ccw
  arc A1 (11.75, -42.5) -> (30.75, -42.5) centre (21.25, -23.5694) ccw
revolve "旋转96" add sketch "草图96" angle 360 about axis through (9.75, -42.5, 0) along (1, 0, 0) separate body makes body 97 in component "scene_go"
sketch "草图97" plane through (0, 0, 0) normal (0, 0, 1) x (1, 0, 0) in component "scene_go"
  line L0 (9.75, -21.25) -> (32.75, -21.25) construction
  arc A0 (30.75, -21.25) -> (11.75, -21.25) centre (21.25, -40.1806) ccw
  arc A1 (11.75, -21.25) -> (30.75, -21.25) centre (21.25, -2.3194) ccw
revolve "旋转97" add sketch "草图97" angle 360 about axis through (9.75, -21.25, 0) along (1, 0, 0) separate body makes body 98 in component "scene_go"
sketch "草图98" plane through (0, 0, 0) normal (0, 0, 1) x (1, 0, 0) in component "scene_go"
  line L0 (9.75, 0) -> (32.75, 0) construction
  arc A0 (30.75, 0) -> (11.75, 0) centre (21.25, -18.9306) ccw
  arc A1 (11.75, 0) -> (30.75, 0) centre (21.25, 18.9306) ccw
revolve "旋转98" add sketch "草图98" angle 360 about axis through (9.75, 0, 0) along (1, 0, 0) separate body makes body 99 in component "scene_go"
sketch "草图99" plane through (0, 0, 0) normal (0, 0, 1) x (1, 0, 0) in component "scene_go"
  line L0 (9.75, 21.25) -> (32.75, 21.25) construction
  arc A0 (30.75, 21.25) -> (11.75, 21.25) centre (21.25, 2.3194) ccw
  arc A1 (11.75, 21.25) -> (30.75, 21.25) centre (21.25, 40.1806) ccw
revolve "旋转99" add sketch "草图99" angle 360 about axis through (9.75, 21.25, 0) along (1, 0, 0) separate body makes body 100 in component "scene_go"
sketch "草图100" plane through (0, 0, 0) normal (0, 0, 1) x (1, 0, 0) in component "scene_go"
  line L0 (9.75, 42.5) -> (32.75, 42.5) construction
  arc A0 (30.75, 42.5) -> (11.75, 42.5) centre (21.25, 23.5694) ccw
  arc A1 (11.75, 42.5) -> (30.75, 42.5) centre (21.25, 61.4306) ccw
revolve "旋转100" add sketch "草图100" angle 360 about axis through (9.75, 42.5, 0) along (1, 0, 0) separate body makes body 101 in component "scene_go"
sketch "草图101" plane through (0, 0, 0) normal (0, 0, 1) x (1, 0, 0) in component "scene_go"
  line L0 (9.75, 63.75) -> (32.75, 63.75) construction
  arc A0 (30.75, 63.75) -> (11.75, 63.75) centre (21.25, 44.8194) ccw
  arc A1 (11.75, 63.75) -> (30.75, 63.75) centre (21.25, 82.6806) ccw
revolve "旋转101" add sketch "草图101" angle 360 about axis through (9.75, 63.75, 0) along (1, 0, 0) separate body makes body 102 in component "scene_go"
sketch "草图102" plane through (0, 0, 0) normal (0, 0, 1) x (1, 0, 0) in component "scene_go"
  line L0 (9.75, 85) -> (32.75, 85) construction
  arc A0 (30.75, 85) -> (11.75, 85) centre (21.25, 66.0694) ccw
  arc A1 (11.75, 85) -> (30.75, 85) centre (21.25, 103.9306) ccw
revolve "旋转102" add sketch "草图102" angle 360 about axis through (9.75, 85, 0) along (1, 0, 0) separate body makes body 103 in component "scene_go"